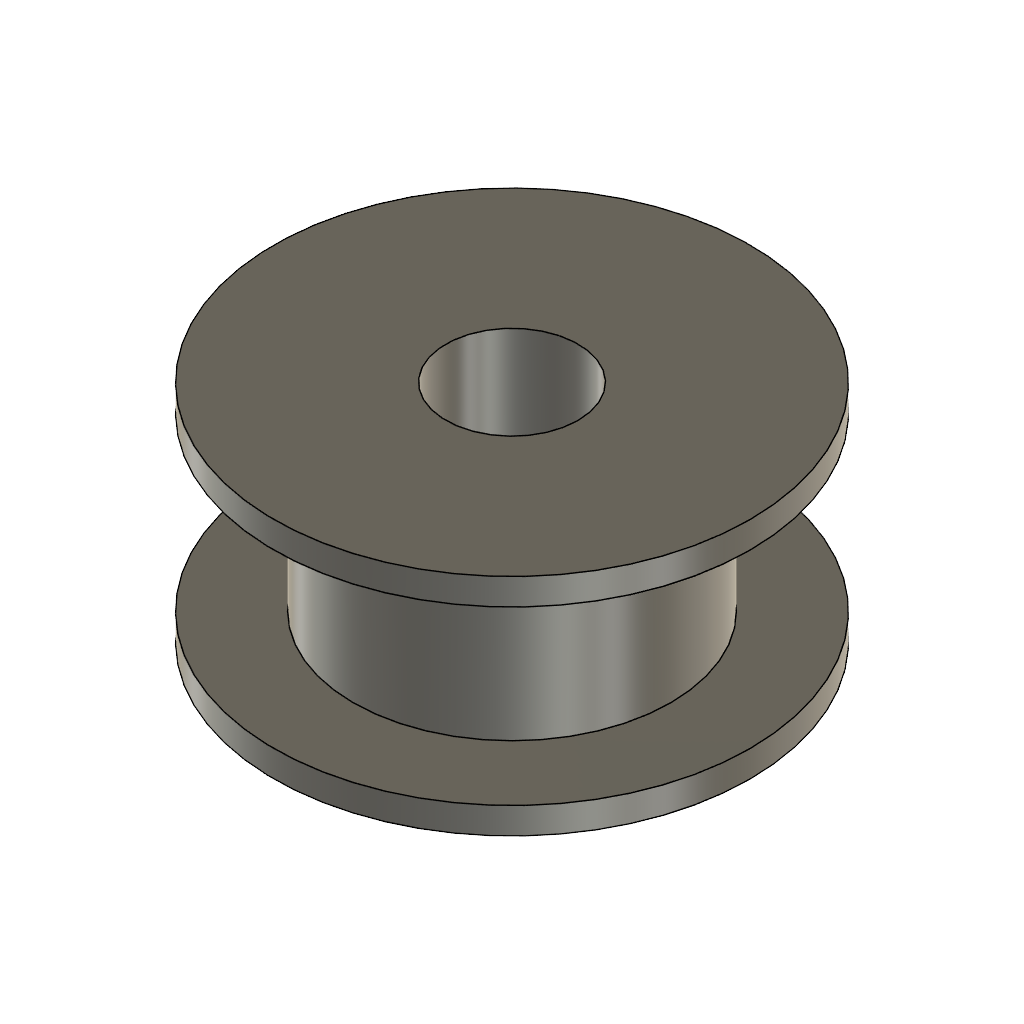
Configuration 1 (Autodesk Fusion 360 archive; units mm, degrees)
design "GT2 Idler Pulley 6mm"
part number: 2026-10-15-13-51-56-063
Autodesk Fusion 360 part; units mm, degrees
note: some values were not read from the file. Set by a fixed rule: the direction of a hole.
sketch "Sketch1" plane through (0, 0, 0) normal (0, 0, 1) x (1, 0, 0)
  circle A0 centre (0, 0) radius 6
  dimension "d1" = 12
  constraint coincident A0.centre origin
  measures "d1" diameter of A0
extrude "Extrude1" add sketch "Sketch1" along normal mid plane 6.5 makes body 1
sketch "Sketch2" plane through (0, 0, 3.25) normal (0, 0, 1) x (-1, 0, 0)
  circle A0 centre (0, 0) radius 6
  circle A1 centre (0, 0) radius 9
  dimension "d4" = 18
  constraint coincident A0.centre A1.centre
  measures "d4" diameter of A1
extrude "Extrude2" add sketch "Sketch2" along normal blind 1 contours A0 | A1 bodies 1
mirror "Mirror1" about plane through (0, 0, 0) normal (0, 0, 1) of "Extrude2"
sketch "Sketch3" plane through (0, 0, 4.25) normal (0, 0, 1) x (-1, 0, 0)
  circle A0 centre (0, 0) radius 9
hole "Hole1" at (0, 0, 4.25) direction (0, 0, -1) diameter 5 end through all bodies 1 1
sketch "Sketch4" plane through (0, 0, 0) normal (0, 0, 1) x (1, 0, 0)
  circle A0 centre (0, 0) radius 10
  dimension "d11" = 20
  constraint coincident A0.centre origin
  measures "d11" diameter of A0
extrude "Extrude3" add sketch "Sketch4" along normal mid plane 9.5 separate body makes body 2
hidden bodies 2
named bodies: "Pulley", "Pocket"

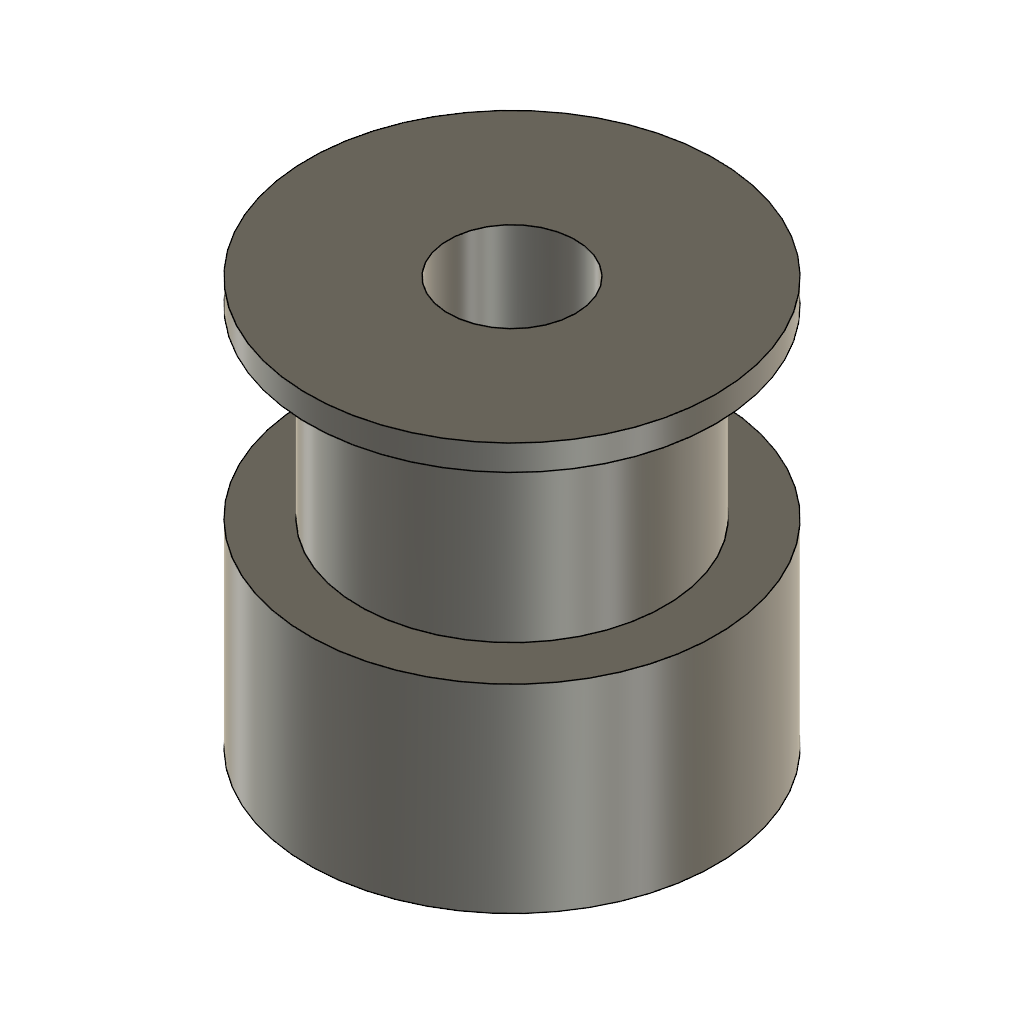
design "GT Drive Pulley 6mm"
part number: 2026-10-15-14-07-30-111
Autodesk Fusion 360 part; units mm, degrees
sketch "Sketch1" plane through (0, 0, 0) normal (0, 0, 1) x (1, 0, 0)
  circle A0 centre (0, 0) radius 6
  dimension "d1" = 12
  constraint coincident A0.centre origin
  measures "d1" diameter of A0
extrude "Extrude1" add sketch "Sketch1" along normal mid plane 7.2 makes body 1
sketch "Sketch2" plane through (0, 0, 3.6) normal (0, 0, 1) x (-1, 0, 0)
  circle A0 centre (0, 0) radius 6
  circle A1 centre (0, 0) radius 8
  dimension "d4" = 16
  constraint coincident A0.centre A1.centre
  measures "d4" diameter of A1
extrude "Extrude2" add sketch "Sketch2" along normal blind 1 contours A0 | A1 bodies 1
sketch "Sketch3" plane through (0, 0, -3.6) normal (0, 0, -1) x (1, 0, 0)
  circle A0 centre (0, 0) radius 6
  circle A1 centre (0, 0) radius 8
  dimension "d7" = 16
  constraint coincident A0.centre A1.centre
  measures "d7" diameter of A1
extrude "Extrude3" add sketch "Sketch3" along normal blind 7.8 contours A0 | A1 bodies 1
sketch "Sketch4" plane through (0, 0, 4.6) normal (0, 0, 1) x (-1, 0, 0)
  circle A0 centre (0, 0) radius 8
hole "Hole1" at (0, 0, 4.6) direction (0, 0, -1) diameter 5 end through all bodies 1 1
sketch "Sketch5" plane through (0, 0, 0) normal (0, 0, 1) x (1, 0, 0)
  circle A0 centre (0, 0) radius 9
  dimension "d12" = 18
  constraint coincident A0.centre origin
  measures "d12" diameter of A0
extrude "Extrude4" add sketch "Sketch5" along normal up to surface (5.6 mm away) and the other way up to surface (12.4 mm away) separate body makes body 2
hidden bodies 2
named bodies: "Pulley", "Pocket"

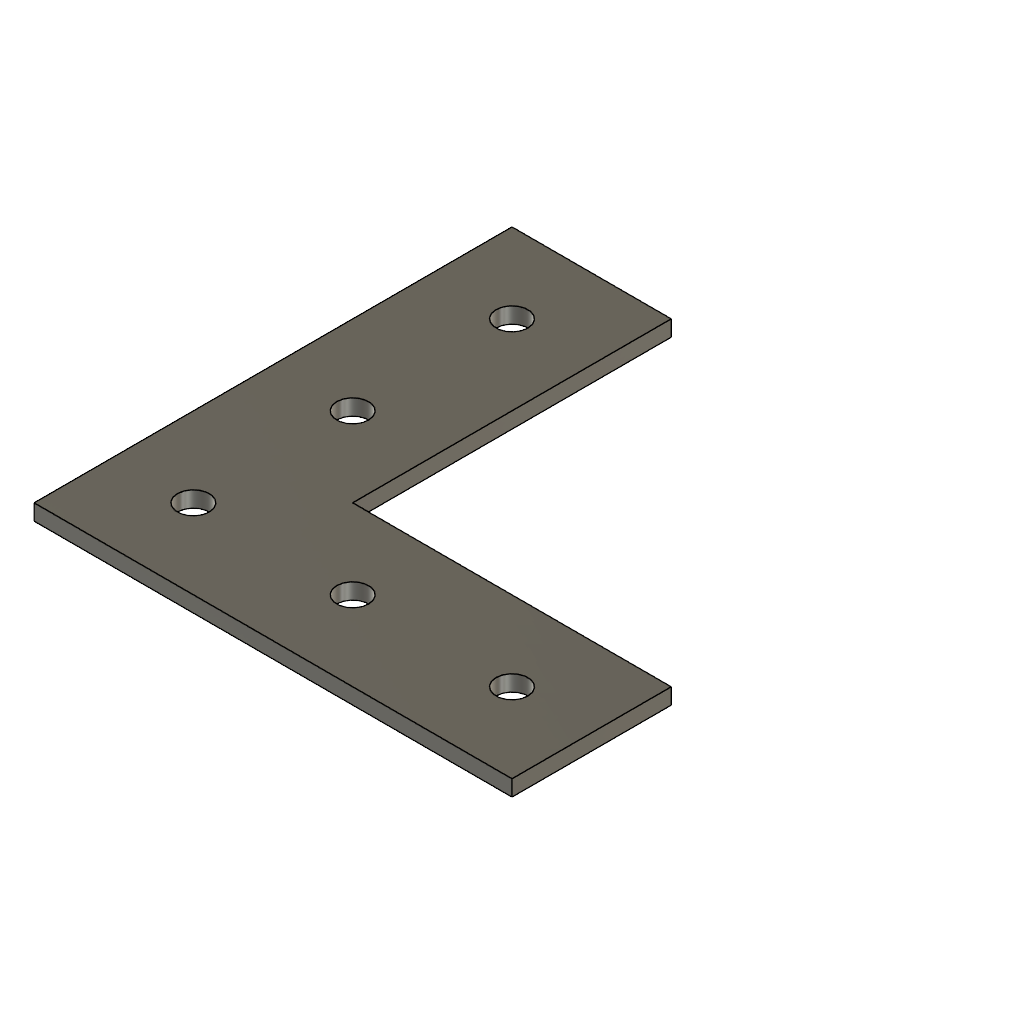
design "MakerBeamXL Right Angle"
part number: 2026-11-18-16-33-52-825
Autodesk Fusion 360 part; units mm, degrees
sketch "Sketch1" plane through (0, 0, 0) normal (0, 0, 1) x (1, 0, 0)
  line L0 (-7.5, 37.5) -> (7.5, 37.5)
  line L1 (7.5, 37.5) -> (7.5, 7.5)
  line L2 (7.5, 7.5) -> (37.5, 7.5)
  line L3 (37.5, 7.5) -> (37.5, -7.5)
  line L4 (37.5, -7.5) -> (-7.5, -7.5)
  line L5 (-7.5, -7.5) -> (-7.5, 37.5)
  point P0 (0, 37.5)
  point P1 (37.5, 0)
  point P2 (15, 0)
  point P3 (30, 0)
  point P4 (0, 15)
  point P5 (15, 15)
  point P6 (30, 15)
  point P7 (0, 30)
  point P8 (15, 30)
  point P9 (30, 30)
  dimension "d1" = 15
  dimension "d2" = 45
  dimension "d5" = 15
  dimension "d6" = 15
  constraint horizontal L0
  constraint perpendicular L0 L1
  constraint perpendicular L1 L2
  constraint perpendicular L2 L3
  constraint perpendicular L3 L4
  constraint vertical L5
  constraint midpoint L0 P0
  constraint midpoint L3 P1
  constraint equal L0 L3
  constraint equal L1 L2
  constraint horizontal origin P1
  constraint vertical origin P0
  measures "d1" distance of L0.start L0.end
  measures "d2" distance of L0.start L4.end
extrude "Extrude1" add sketch "Sketch1" along normal blind 1.5
hole "Hole1" at (0, 30, 0) at (0, 15, 0) at (0, 0, 0) at (15, 0, 0) at (30, 0, 0) direction (0, 0, 1) diameter 3 end through all

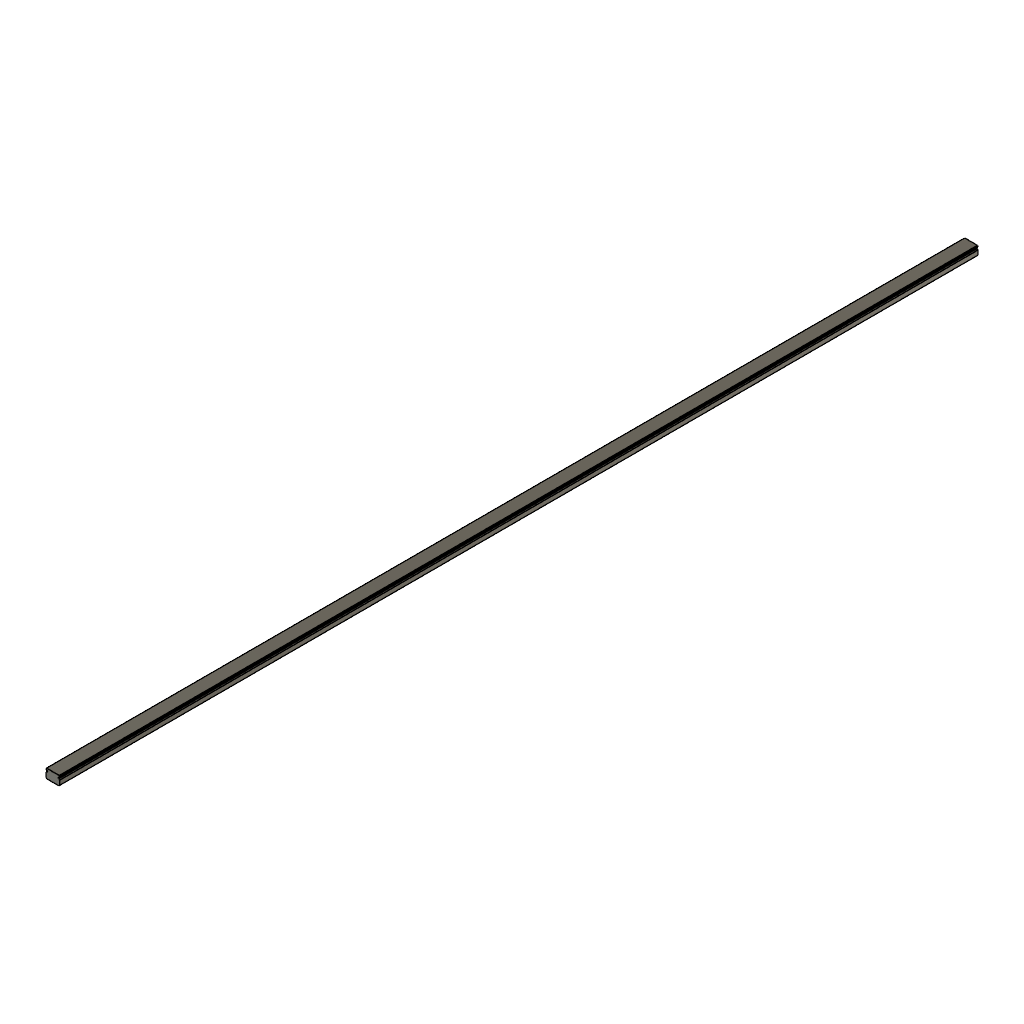
design "MGN15 Rail"
part number: 2026-10-15-13-23-19-019
Autodesk Fusion 360 part; units mm, degrees
sketch "Sketch1" plane through (0, 0, 0) normal (0, 1, 0) x (1, 0, 0)
  line L0 (-7.5, 0) -> (7.5, 0)
  line L1 (7.5, 0) -> (7.5, 10)
  line L2 (7.5, 10) -> (-7.5, 10)
  line L3 (-7.5, 10) -> (-7.5, 0)
  line L4 (-7.5, 0) -> (7.5, 10) construction
  line L5 (7.5, 0) -> (-7.5, 10) construction
  point P0 (0, 5)
  dimension "d1" = 15
  dimension "d2" = 10
  constraint horizontal L0
  constraint perpendicular L0 L1
  constraint parallel L0 L2
  constraint parallel L1 L3
  constraint coincident L4 P0
  constraint coincident L5 P0
  constraint vertical origin P0
  constraint coincident origin L0
  measures "d1" distance of L1.end L2.end
  measures "d2" distance of L0.start L2.end
extrude "Extrude1" add sketch "Sketch1" along normal mid plane 1000
sketch "Sketch2" plane through (0, 0, 0) normal (0, 1, 0) x (1, 0, 0)
  line L0 (-7.5, 0) -> (-7.5, 10)
  line L1 (-7.5, 10) -> (7.5, 10)
  line L2 (7.5, 10) -> (7.5, 0)
  line L3 (7.5, 0) -> (-7.5, 0)
  line L4 (7.5, 2.2) -> (5.8, 2.2)
  line L5 (5.8, 2.2) -> (5.8, 3.2)
  line L6 (5.8, 3.2) -> (7.5, 3.2)
  line L7 (7.5, 3.2) -> (7.5, 2.2)
  point P0 (5.8, 2.7)
  dimension "d5" = 7.3
  dimension "d6" = 1.7
  dimension "d7" = 1
  constraint horizontal L4
  constraint vertical L5
  constraint horizontal L6
  constraint vertical L7
  constraint coincident L2 L4.start
  constraint midpoint L5 P0
  measures "d5" distance of L1 P0
  measures "d6" distance of L5.end L6.end
  measures "d7" distance of L4.end L5.end
extrude "Extrude2" cut sketch "Sketch2" along normal through all and the other way through all contours L2 L4 L5 L6 L7
mirror "Mirror1" about plane through (0, 0, 0) normal (1, 0, 0) of "Extrude2"
chamfer "Chamfer1" distance 0.5 angle 45 2 edges at (-7.5, 0, 0) (7.5, 0, 0)
chamfer "Chamfer2" distance 0.9 angle 45 2 edges at (-7.5, 0, -10) (7.5, 0, -10)
chamfer "Chamfer3" distance 0.9 angle 45 4 edges at (-7.5, 0, -3.2) (-7.5, 0, -2.2) (7.5, 0, -3.2) (7.5, 0, -2.2)
fillet "Fillet1" radius 0.3 4 edges at (5.8, 0, -2.2) (5.8, 0, -3.2) (-5.8, 0, -2.2) (-5.8, 0, -3.2)

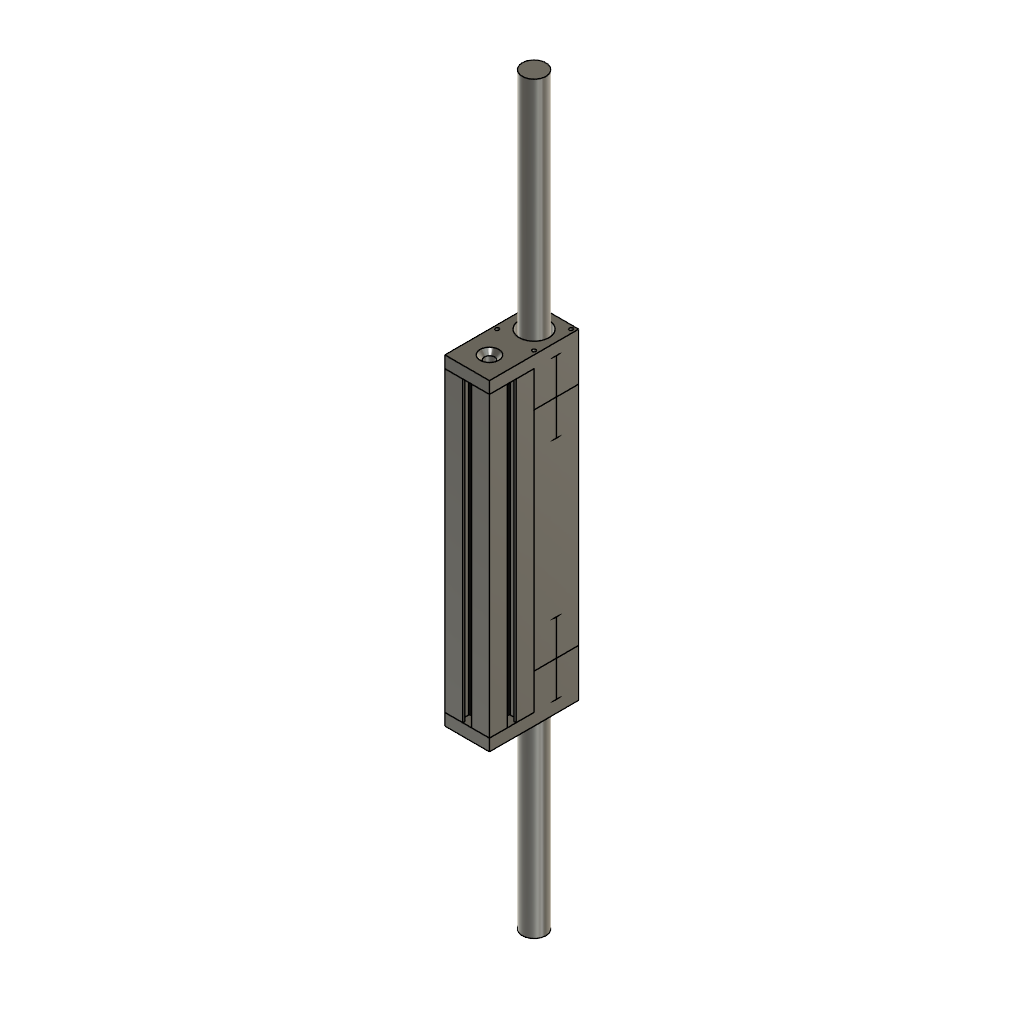
design "LM8UUonMakerBeamXL100mm"
part number: 2026-11-18-12-16-41-758
Autodesk Fusion 360 part; units mm, degrees
sketch "Sketch1" plane through (0, 0, 0) normal (0, 0, 1) x (1, 0, 0)
  line L0 (-7.5, 7.5) -> (7.5, 7.5)
  line L1 (7.5, 7.5) -> (7.5, -7.5)
  line L2 (7.5, -7.5) -> (-7.5, -7.5)
  line L3 (-7.5, -7.5) -> (-7.5, 7.5)
  line L4 (-7.5, 7.5) -> (7.5, -7.5) construction
  line L5 (7.5, 7.5) -> (-7.5, -7.5) construction
  line L6 (-1.5, 7.5) -> (1.5, 7.5)
  line L7 (1.5, 7.5) -> (1.5, 2.5)
  line L8 (1.5, 2.5) -> (-1.5, 2.5)
  line L9 (-1.5, 2.5) -> (-1.5, 7.5)
  line L10 (-1.5, 7.5) -> (1.5, 2.5) construction
  line L11 (1.5, 7.5) -> (-1.5, 2.5) construction
  line L12 (-2.75, 6.5) -> (2.75, 6.5)
  line L13 (2.75, 6.5) -> (2.75, 4)
  line L14 (2.75, 4) -> (-2.75, 4)
  line L15 (-2.75, 4) -> (-2.75, 6.5)
  line L16 (-2.75, 6.5) -> (2.75, 4) construction
  line L17 (2.75, 6.5) -> (-2.75, 4) construction
  point P0 (0, 5)
  point P1 (0, 5.25)
  dimension "d1" = 15
  dimension "d2" = 3
  dimension "d3" = 5
  dimension "d4" = 5.5
  dimension "d5" = 1
  dimension "d6" = 2.5
  constraint horizontal L0
  constraint perpendicular L0 L1
  constraint parallel L0 L2
  constraint parallel L1 L3
  constraint coincident L4 origin
  constraint coincident L5 origin
  constraint equal L0 L3
  constraint horizontal L6
  constraint perpendicular L6 L7
  constraint parallel L6 L8
  constraint parallel L7 L9
  constraint coincident L10 P0
  constraint coincident L11 P0
  constraint coincident L0 L6.start
  constraint horizontal L12
  constraint perpendicular L12 L13
  constraint parallel L12 L14
  constraint parallel L13 L15
  constraint coincident L16 P1
  constraint coincident L17 P1
  constraint vertical origin P0
  constraint vertical origin P1
  measures "d1" distance of L0.start L0.end
  measures "d2" distance of L7 L9
  measures "d3" distance of L6.start L8.end
  measures "d4" distance of L13.end L14.end
  measures "d5" distance of L0 L12
  measures "d6" distance of L12.end L13.end
extrude "Extrude1" add sketch "Sketch1" along normal mid plane 100 makes body 1
extrude "Extrude2" cut sketch "Sketch1" along normal through all and the other way through all contours L0 L6 L7 L9 L12 | L7 L9 L12 L14 | L9 L12 L14 L15 | L7 L12 L13 L14 | L7 L8 L9 L14 bodies 1
fillet "Fillet1" radius 0.25 12 edges at (-1.5, 6.5, 0) (-1.5, 7.5, 0) (-2.75, 6.5, 0) (-1.5, 4, 0) (1.5, 6.5, 0) (1.5, 7.5, 0) (2.75, 6.5, 0) (1.5, 4, 0) (2.75, 4, 0) (1.5, 2.5, 0) (-1.5, 2.5, 0) (-2.75, 4, 0) on bodies 1
pattern_circular "C-Pattern2" count 4 over 360 about axis through (0, 0, 1.75) along (0, 0, 1) of "Extrude2", "Fillet1"
sketch "Sketch2" plane through (0, 0, 50) normal (0, 0, 1) x (-1, 0, 0)
  line L0 (-7.5, -1.5) -> (-7.5, -7.5)
  line L1 (-7.5, -7.5) -> (-1.75, -7.5)
  line L2 (-1.5, -7.25) -> (-1.5, -6.75)
  line L3 (-1.75, -6.5) -> (-2.5, -6.5)
  line L4 (-2.75, -6.25) -> (-2.75, -4.25)
  line L5 (-2.5, -4) -> (-1.75, -4)
  line L6 (-1.5, -3.75) -> (-1.5, -2.75)
  line L7 (-1.25, -2.5) -> (1.25, -2.5)
  line L8 (1.5, -2.75) -> (1.5, -3.75)
  line L9 (1.75, -4) -> (2.5, -4)
  line L10 (2.75, -4.25) -> (2.75, -6.25)
  line L11 (2.5, -6.5) -> (1.75, -6.5)
  line L12 (1.5, -6.75) -> (1.5, -7.25)
  line L13 (7.5, -7.5) -> (7.5, -1.5)
  line L14 (7.5, 7.5) -> (1.5, 7.5)
  line L15 (-7.5, 7.5) -> (-7.5, 1.5)
  arc A0 (-4, 1.75) -> (-3.75, 1.5) centre (-3.75, 1.75) ccw
  line L16 (-3.75, 1.5) -> (-2.75, 1.5)
  arc A1 (-2.5, 1.25) -> (-2.75, 1.5) centre (-2.75, 1.25) ccw
  line L17 (-2.5, 1.25) -> (-2.5, -1.25)
  arc A2 (-2.75, -1.5) -> (-2.5, -1.25) centre (-2.75, -1.25) ccw
  line L18 (-2.75, -1.5) -> (-3.75, -1.5)
  arc A3 (-3.75, -1.5) -> (-4, -1.75) centre (-3.75, -1.75) ccw
  line L19 (-4, -1.75) -> (-4, -2.5)
  arc A4 (-4.25, -2.75) -> (-4, -2.5) centre (-4.25, -2.5) ccw
  line L20 (-4.25, -2.75) -> (-6.25, -2.75)
  arc A5 (-6.5, -2.5) -> (-6.25, -2.75) centre (-6.25, -2.5) ccw
  line L21 (-6.5, -2.5) -> (-6.5, -1.75)
  arc A6 (-6.5, -1.75) -> (-6.75, -1.5) centre (-6.75, -1.75) ccw
  line L22 (-6.75, -1.5) -> (-7.5, -1.5)
  arc A7 (-1.75, -7.5) -> (-1.5, -7.25) centre (-1.75, -7.25) ccw
  arc A8 (-1.5, -6.75) -> (-1.75, -6.5) centre (-1.75, -6.75) ccw
  arc A9 (-2.75, -6.25) -> (-2.5, -6.5) centre (-2.5, -6.25) ccw
  arc A10 (-2.5, -4) -> (-2.75, -4.25) centre (-2.5, -4.25) ccw
  arc A11 (-1.75, -4) -> (-1.5, -3.75) centre (-1.75, -3.75) ccw
  arc A12 (-1.25, -2.5) -> (-1.5, -2.75) centre (-1.25, -2.75) ccw
  arc A13 (1.5, -2.75) -> (1.25, -2.5) centre (1.25, -2.75) ccw
  arc A14 (1.5, -3.75) -> (1.75, -4) centre (1.75, -3.75) ccw
  arc A15 (2.75, -4.25) -> (2.5, -4) centre (2.5, -4.25) ccw
  arc A16 (2.5, -6.5) -> (2.75, -6.25) centre (2.5, -6.25) ccw
  arc A17 (1.75, -6.5) -> (1.5, -6.75) centre (1.75, -6.75) ccw
  arc A18 (1.5, -7.25) -> (1.75, -7.5) centre (1.75, -7.25) ccw
  line L23 (1.75, -7.5) -> (7.5, -7.5)
  line L24 (7.5, -1.5) -> (6.75, -1.5)
  arc A19 (6.75, -1.5) -> (6.5, -1.75) centre (6.75, -1.75) ccw
  line L25 (6.5, -1.75) -> (6.5, -2.5)
  arc A20 (6.25, -2.75) -> (6.5, -2.5) centre (6.25, -2.5) ccw
  line L26 (6.25, -2.75) -> (4.25, -2.75)
  arc A21 (4, -2.5) -> (4.25, -2.75) centre (4.25, -2.5) ccw
  line L27 (4, -2.5) -> (4, -1.75)
  arc A22 (4, -1.75) -> (3.75, -1.5) centre (3.75, -1.75) ccw
  line L28 (3.75, -1.5) -> (2.75, -1.5)
  arc A23 (2.5, -1.25) -> (2.75, -1.5) centre (2.75, -1.25) ccw
  line L29 (2.5, -1.25) -> (2.5, 1.25)
  arc A24 (2.75, 1.5) -> (2.5, 1.25) centre (2.75, 1.25) ccw
  line L30 (2.75, 1.5) -> (3.75, 1.5)
  arc A25 (3.75, 1.5) -> (4, 1.75) centre (3.75, 1.75) ccw
  line L31 (4, 1.75) -> (4, 2.5)
  arc A26 (4.25, 2.75) -> (4, 2.5) centre (4.25, 2.5) ccw
  line L32 (4.25, 2.75) -> (6.25, 2.75)
  arc A27 (6.5, 2.5) -> (6.25, 2.75) centre (6.25, 2.5) ccw
  line L33 (6.5, 2.5) -> (6.5, 1.75)
  arc A28 (6.5, 1.75) -> (6.75, 1.5) centre (6.75, 1.75) ccw
  line L34 (6.75, 1.5) -> (7.5, 1.5)
  line L35 (7.5, 1.5) -> (7.5, 7.5)
  line L36 (1.5, 7.5) -> (1.5, 6.75)
  arc A29 (1.5, 6.75) -> (1.75, 6.5) centre (1.75, 6.75) ccw
  line L37 (1.75, 6.5) -> (2.5, 6.5)
  arc A30 (2.75, 6.25) -> (2.5, 6.5) centre (2.5, 6.25) ccw
  line L38 (2.75, 6.25) -> (2.75, 4.25)
  arc A31 (2.5, 4) -> (2.75, 4.25) centre (2.5, 4.25) ccw
  line L39 (2.5, 4) -> (1.75, 4)
  arc A32 (1.75, 4) -> (1.5, 3.75) centre (1.75, 3.75) ccw
  line L40 (1.5, 3.75) -> (1.5, 2.75)
  arc A33 (1.25, 2.5) -> (1.5, 2.75) centre (1.25, 2.75) ccw
  line L41 (1.25, 2.5) -> (-1.25, 2.5)
  arc A34 (-1.5, 2.75) -> (-1.25, 2.5) centre (-1.25, 2.75) ccw
  line L42 (-1.5, 2.75) -> (-1.5, 3.75)
  arc A35 (-1.5, 3.75) -> (-1.75, 4) centre (-1.75, 3.75) ccw
  line L43 (-1.75, 4) -> (-2.5, 4)
  arc A36 (-2.75, 4.25) -> (-2.5, 4) centre (-2.5, 4.25) ccw
  line L44 (-2.75, 4.25) -> (-2.75, 6.25)
  arc A37 (-2.5, 6.5) -> (-2.75, 6.25) centre (-2.5, 6.25) ccw
  line L45 (-2.5, 6.5) -> (-1.75, 6.5)
  arc A38 (-1.75, 6.5) -> (-1.5, 6.75) centre (-1.75, 6.75) ccw
  line L46 (-1.5, 6.75) -> (-1.5, 7.5)
  line L47 (-1.5, 7.5) -> (-7.5, 7.5)
  line L48 (-7.5, 1.5) -> (-6.75, 1.5)
  arc A39 (-6.75, 1.5) -> (-6.5, 1.75) centre (-6.75, 1.75) ccw
  line L49 (-6.5, 1.75) -> (-6.5, 2.5)
  arc A40 (-6.25, 2.75) -> (-6.5, 2.5) centre (-6.25, 2.5) ccw
  line L50 (-6.25, 2.75) -> (-4.25, 2.75)
  arc A41 (-4, 2.5) -> (-4.25, 2.75) centre (-4.25, 2.5) ccw
  line L51 (-4, 2.5) -> (-4, 1.75)
hole "Hole1" at (0, 0, 50) direction (0, 0, -1) diameter 2.529 end through all bodies 1 1
sketch "Sketch3" plane through (0, 0, 0) normal (0, 0, 1) x (1, 0, 0)
  circle A0 centre (0, 15) radius 7.5
  circle A1 centre (0, 15) radius 4
  dimension "d22" = 15
  dimension "d23" = 15
  dimension "d24" = 8
  constraint vertical origin A0.centre
  constraint concentric A0 A1
  measures "d22" diameter of A0
  measures "d23" distance of origin A0.centre
  measures "d24" diameter of A1
extrude "Extrude3" add sketch "Sketch3" against normal blind 24 from surface at 50 separate body makes body 2
mirror "Mirror1" about plane through (0, 0, 0) normal (0, 0, 1) of bodies 2 makes body 3
extrude "Extrude4" add sketch "Sketch3" along normal blind 129.5 and the other way blind 120.5 separate body contours A1 makes body 4
sketch "Sketch4" plane through (0, 0, 0) normal (0, 0, 1) x (1, 0, 0)
  line L0 (1.5, 7.25) -> (1.5, 6.75)
  arc A0 (1.5, 6.75) -> (1.75, 6.5) centre (1.75, 6.75) ccw
  line L1 (1.75, 6.5) -> (2.5, 6.5)
  arc A1 (2.75, 6.25) -> (2.5, 6.5) centre (2.5, 6.25) ccw
  line L2 (2.75, 6.25) -> (2.75, 4.25)
  arc A2 (2.5, 4) -> (2.75, 4.25) centre (2.5, 4.25) ccw
  line L3 (2.5, 4) -> (1.75, 4)
  line L4 (-1.75, 4) -> (-2.5, 4)
  arc A3 (-2.75, 4.25) -> (-2.5, 4) centre (-2.5, 4.25) ccw
  line L5 (-2.75, 4.25) -> (-2.75, 6.25)
  arc A4 (-2.5, 6.5) -> (-2.75, 6.25) centre (-2.5, 6.25) ccw
  line L6 (-2.5, 6.5) -> (-1.75, 6.5)
  arc A5 (-1.75, 6.5) -> (-1.5, 6.75) centre (-1.75, 6.75) ccw
  line L7 (-1.5, 6.75) -> (-1.5, 7.25)
  circle A6 centre (0, 15) radius 4
  circle A7 centre (0, 15) radius 7.5
  line L8 (-2.55, 4.25) -> (-2.55, 6.25)
  arc A8 (-2.55, 4.25) -> (-2.5, 4.2) centre (-2.5, 4.25) ccw
  line L9 (2.5, 4.2) -> (-2.5, 4.2)
  arc A9 (2.5, 4.2) -> (2.55, 4.25) centre (2.5, 4.25) ccw
  line L10 (2.55, 6.25) -> (2.55, 4.25)
  line L11 (1.3, 7.6135) -> (1.3, 6.75)
  line L12 (-1.3, 6.75) -> (-1.3, 7.6135)
  line L13 (-7.5, 22.5) -> (7.5, 22.5)
  line L14 (7.5, 22.5) -> (7.5, -7.5)
  line L15 (7.5, -7.5) -> (-7.5, -7.5)
  line L16 (-7.5, -7.5) -> (-7.5, 22.5)
  line L17 (-7.5, 22.5) -> (7.5, -7.5) construction
  line L18 (7.5, 22.5) -> (-7.5, -7.5) construction
  arc A10 (-2.3, 6.5) -> (-2.55, 6.25) centre (-2.3, 6.25) ccw
  arc A11 (2.55, 6.25) -> (2.3, 6.5) centre (2.3, 6.25) ccw
  arc A12 (-1.55, 6.5) -> (-1.3, 6.75) centre (-1.55, 6.75) ccw
  arc A13 (1.3, 6.75) -> (1.55, 6.5) centre (1.55, 6.75) ccw
  line L19 (-2.3, 6.5) -> (-1.55, 6.5)
  line L20 (1.55, 6.5) -> (2.3, 6.5)
  line L21 (-7.5, 7.5) -> (-1.3, 7.5)
  line L22 (7.5, 7.5) -> (1.3, 7.5)
  circle A14 centre (0, 15) radius 5
  point P0 (0, 7.5)
  dimension "d32" = 0.2
  dimension "d33" = 7.5
  dimension "d34" = 15
  dimension "d35" = 10
  constraint horizontal L13
  constraint perpendicular L13 L14
  constraint parallel L13 L15
  constraint parallel L14 L16
  constraint coincident L17 P0
  constraint coincident L18 P0
  constraint coincident A7 P0
  constraint vertical origin P0
  constraint coincident A7 L12.end
  constraint coincident A7 L11.start
  constraint coincident L6 A10.start
  constraint coincident L1 A11.end
  constraint tangent L10 A11
  constraint tangent L8 A10
  constraint tangent L6 A10
  constraint tangent L1 A11
  constraint horizontal A1.start L10.start
  constraint horizontal A4.centre L8.end
  constraint tangent L12 A12
  constraint tangent L11 A13
  constraint tangent A13 L20
  constraint horizontal L20
  constraint horizontal L19
  constraint tangent A12 L19
  constraint horizontal A5.end L12.start
  constraint horizontal L0.end L11.end
  constraint midpoint L16 L21.start
  constraint coincident L12 L21.end
  constraint perpendicular L12 L21
  constraint midpoint L14 L22.start
  constraint coincident L11 L22.end
  constraint perpendicular L11 L22
  constraint concentric A6 A14
  measures "d33" distance of origin L15
  measures "d34" distance of L14.end L15.end
  measures "d35" diameter of A14
extrude "Extrude5" add sketch "Sketch4" along normal mid plane 52 separate body contours L1 L6 A7 L8 A8 L9 A9 L10 L11 L12 A10 A11 A12 A13 L19 L20 | A7 L11 L14 L22 | A7 | A7 L12 L16 L21 | A7 L13 L14 | A7 L13 L16 makes body 5
extrude "Extrude6" add sketch "Sketch4" along normal mid plane 76 contours L1 L6 A7 L8 A8 L9 A9 L10 L11 L12 A10 A11 A12 A13 L19 L20 | A7 L11 L14 L22 | A7 L12 L16 L21 | A7 L13 L14 | A7 L13 L16 bodies 5
extrude "Extrude7" add sketch "Sketch4" along normal blind 4 from surface at 50 separate body contours L1 L6 L8 A8 L9 A9 L10 L11 L12 L14 L15 L16 A10 A11 A12 A13 L19 L20 L21 L22 | L1 L6 A7 L8 A8 L9 A9 L10 L11 L12 A10 A11 A12 A13 L19 L20 | A7 L11 L14 L22 | A7 | A7 L12 L16 L21 | A7 L13 L14 | A7 L13 L16 makes body 6
sketch "Sketch5" plane through (0, 0, 54) normal (0, 0, 1) x (-1, 0, 0)
  circle A0 centre (0, -15) radius 5
  line L0 (7.5, 7.5) -> (-7.5, 7.5)
  line L1 (-7.5, 7.5) -> (-7.5, -22.5)
  line L2 (-7.5, -22.5) -> (7.5, -22.5)
  line L3 (7.5, -22.5) -> (7.5, 7.5)
hole "Hole2" at (0, 0, 54) direction (0, 0, -1) diameter 3.4 end through all countersink diameter 6.3 countersink angle 90 bodies 6 6
extrude "Extrude8" add sketch "Sketch4" against normal blind 12 from surface at 50 contours L1 L6 A7 L8 A8 L9 A9 L10 L11 L12 A10 A11 A12 A13 L19 L20 | A7 L11 L14 L22 | A7 L12 L16 L21 | A7 L13 L14 | A7 L13 L16 bodies 6
sketch "Sketch6" plane through (0, 22.5, 0) normal (0, -1, 0) x (1, 0, 0)
  line L0 (2.5, -38) -> (2.5, 38)
  line L1 (2.5, 38) -> (-2.5, 38)
  line L2 (-2.5, 38) -> (-2.5, -38)
  line L3 (-2.5, -38) -> (2.5, -38)
  line L4 (-7.5, -26) -> (7.5, -26)
  line L5 (7.5, 26) -> (-7.5, 26)
  line L6 (-7.5, -38) -> (-7.5, 38)
  line L7 (-7.5, 38) -> (0, 38)
  line L8 (0, 38) -> (7.5, 38)
  line L9 (7.5, 38) -> (7.5, -38)
  line L10 (7.5, -38) -> (0, -38)
  line L11 (0, -38) -> (-7.5, -38)
  line L12 (0, 38) -> (0, 26)
  line L13 (0, -38) -> (0, -26)
  line L14 (0, 26) -> (0, 38)
  line L15 (0, -26) -> (0, -38)
  point P0 (0, -20)
  point P1 (0, 20)
  dimension "d52" = 0
  dimension "d53" = 20
hole "Hole4" at (0, 22.5, -20) at (0, 22.5, 0) at (0, 22.5, 20) direction (0, -1, 0) diameter 2.529 end through all bodies 1 5
sketch "Sketch7" plane through (0, 0, 54) normal (0, 0, 1) x (-1, 0, 0)
  circle A0 centre (0, 0) radius 3.15
  circle A1 centre (0, -15) radius 5
  line L0 (7.5, 7.5) -> (-7.5, 7.5)
  line L1 (-7.5, 7.5) -> (-7.5, -22.5)
  line L2 (-7.5, -22.5) -> (7.5, -22.5)
  line L3 (7.5, -22.5) -> (7.5, 7.5)
  circle A2 centre (0, -15) radius 7.5
  line L4 (7.5, -7.5) -> (1.3, -7.5)
  line L5 (-7.5, -7.5) -> (-1.3, -7.5)
  circle A3 centre (6.2132, -21.2132) radius 1.2868
  line L6 (6.2132, -21.2132) -> (-6.2132, -21.2132)
  line L7 (-6.2132, -21.2132) -> (-6.2132, -8.7868)
  line L8 (-6.2132, -8.7868) -> (6.2132, -8.7868)
  line L9 (6.2132, -8.7868) -> (6.2132, -21.2132)
  line L10 (6.2132, -21.2132) -> (-6.2132, -8.7868) construction
  line L11 (-6.2132, -21.2132) -> (6.2132, -8.7868) construction
  line L12 (7.5, -22.5) -> (-7.5, -22.5)
  line L13 (7.5, 7.5) -> (7.5, -22.5)
  point P0 (0, -15)
  constraint horizontal L6
  constraint perpendicular L6 L7
  constraint parallel L6 L8
  constraint parallel L7 L9
  constraint coincident L10 P0
  constraint coincident L11 P0
  constraint coincident A3.centre L6.start
  constraint coincident P0 A1.centre
  constraint tangent A3 L12
  constraint tangent A3 L13
  constraint tangent A2 A3
hole "Hole5" at (-6.2132, 21.2132, 54) at (6.2132, 21.2132, 54) at (6.2132, 8.7868, 54) at (-6.2132, 8.7868, 54) direction (0, 0, -1) diameter 1.2 end through all bodies 5 5 6
mirror "Mirror2" about plane through (0, 0, 0) normal (0, 0, 1) of bodies 6 makes body 7
